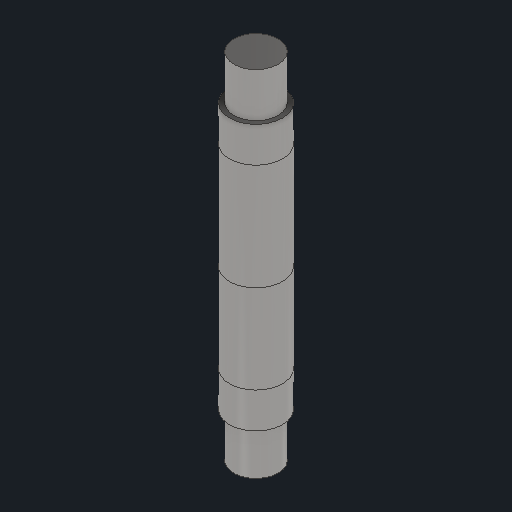
# Autodesk Inventor part: E1
Saved by Autodesk Inventor 2027 (Build 310192000, 192)
## iProperties
Created: 2026-11-10
Part Number: E1
Material: Genérico
Description: Eixo E1
Document SubType Name: Modeling
Designer: Bruno Madela
Mass: 8.35664 g
Surface Area: 31.1646 cm^2
Volume: 8.35664 cm^3
Density: 1 g/cm^3
Appearance: Aço - Polido
Author: Bruno Madela
Autodesk Inventor part; units mm, degrees
sketch "Esboço1" plane through (0, 0, 0) normal (0, 0, 1) x (1, 0, 0)
  line L0 (0, 0) -> (5, 0)
  line L1 (5, 0) -> (5, 10)
  line L2 (5, 10) -> (6, 10)
  line L3 (6, 10) -> (6, 18)
  line L4 (6, 18) -> (6, 38)
  line L5 (6, 38) -> (6, 62)
  line L6 (6, 62) -> (6, 70)
  line L7 (6, 70) -> (5, 70)
  line L8 (5, 70) -> (5, 80)
  line L9 (5, 80) -> (0, 80)
  line L10 (0, 80) -> (0, 0)
  constraints: 22 end point
revolve "Eixo E1 (revolucao 80 mm)" add sketch "Esboço1" angle 360 about axis through (0, 80, 0) along (0, -1, 0)
ref_plane "Plano_divisao_18" through (0, 18, 0) normal (0, 1, 0) x (-1, 0, 0)
split_face "Divisao_trecho_18"
ref_plane "Plano_divisao_38" through (0, 38, 0) normal (0, 1, 0) x (-1, 0, 0)
split_face "Divisao_trecho_38"
ref_plane "Plano_divisao_62" through (0, 62, 0) normal (0, 1, 0) x (-1, 0, 0)
split_face "Divisao_trecho_62"
